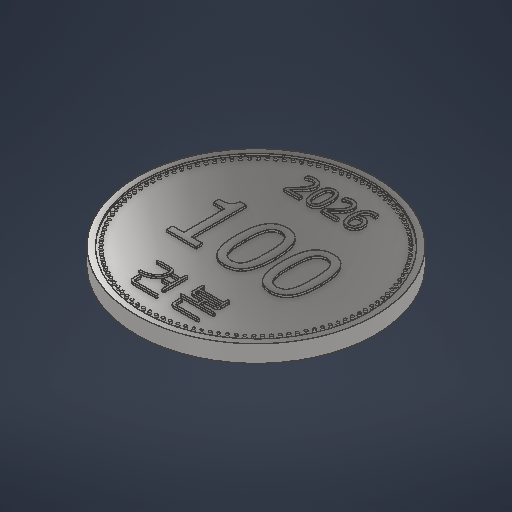
# Autodesk Inventor part: 비교용 100원 모델링
Saved by Autodesk Inventor 2027.1 (Build 311270010, 270A)
## iProperties
Created: 2026-09-27
Part Number: 비교용 100원 모델링
Material: 스테인리스스틸
Document SubType Name: Modeling
Designer: work
Density: 8 g/cm^3
Appearance: 반연마
Author: work
Autodesk Inventor part; units mm, degrees
ref_plane "YZ Plane" through (0, 0, 0) normal (1, 0, 0) x (0, 1, 0)
ref_plane "XZ Plane" through (0, 0, 0) normal (0, 1, 0) x (-1, 0, 0)
ref_plane "XY Plane" through (0, 0, 0) normal (0, 0, 1) x (1, 0, 0)
sketch "스케치1" plane through (0, 0, 0) normal (0, 1, 0) x (-1, 0, 0)
  circle A0 centre (0, 0) radius 12
  dimension "d0" = 24
  constraints: 1 centre point, 1 coincident
  measures "d0" diameter of A0
extrude "돌출1" add sketch "스케치1" along normal blind 1.5
sketch "스케치2" plane through (0, 1.5, 0) normal (0, 1, 0) x (1, 0, 0)
  circle A0 centre (0, 0) radius 12 projected
  circle A1 centre (0, 0) radius 11.4
  line L0 (0, 0) -> (-11, 0) construction
  circle A2 centre (-11, 0) radius 0.15
  line L1 (0, 0) -> (-10.9821, -0.628) construction
  circle A3 centre (-10.9821, -0.628) radius 0.15
  line L2 (0, 0) -> (-10.9283, -1.2539) construction
  circle A4 centre (-10.9283, -1.2539) radius 0.15
  line L3 (0, 0) -> (-10.8389, -1.8757) construction
  circle A5 centre (-10.8389, -1.8757) radius 0.15
  line L4 (0, 0) -> (-10.7141, -2.4915) construction
  circle A6 centre (-10.7141, -2.4915) radius 0.15
  line L5 (0, 0) -> (-10.5544, -3.0991) construction
  circle A7 centre (-10.5544, -3.0991) radius 0.15
  line L6 (0, 0) -> (-10.3603, -3.6965) construction
  circle A8 centre (-10.3603, -3.6965) radius 0.15
  line L7 (0, 0) -> (-10.1324, -4.282) construction
  circle A9 centre (-10.1324, -4.282) radius 0.15
  line L8 (0, 0) -> (-9.8714, -4.8534) construction
  circle A10 centre (-9.8714, -4.8534) radius 0.15
  line L9 (0, 0) -> (-9.5782, -5.4091) construction
  circle A11 centre (-9.5782, -5.4091) radius 0.15
  line L10 (0, 0) -> (-9.2538, -5.947) construction
  circle A12 centre (-9.2538, -5.947) radius 0.15
  line L11 (0, 0) -> (-8.8992, -6.4656) construction
  circle A13 centre (-8.8992, -6.4656) radius 0.15
  line L12 (0, 0) -> (-8.5156, -6.9631) construction
  circle A14 centre (-8.5156, -6.9631) radius 0.15
  line L13 (0, 0) -> (-8.1042, -7.4379) construction
  circle A15 centre (-8.1042, -7.4379) radius 0.15
  line L14 (0, 0) -> (-7.6663, -7.8884) construction
  circle A16 centre (-7.6663, -7.8884) radius 0.15
  line L15 (0, 0) -> (-7.2035, -8.3132) construction
  circle A17 centre (-7.2035, -8.3132) radius 0.15
  line L16 (0, 0) -> (-6.7171, -8.7109) construction
  circle A18 centre (-6.7171, -8.7109) radius 0.15
  line L17 (0, 0) -> (-6.2089, -9.0802) construction
  circle A19 centre (-6.2089, -9.0802) radius 0.15
  line L18 (0, 0) -> (-5.6804, -9.4198) construction
  circle A20 centre (-5.6804, -9.4198) radius 0.15
  line L19 (0, 0) -> (-5.1333, -9.7288) construction
  circle A21 centre (-5.1333, -9.7288) radius 0.15
  line L20 (0, 0) -> (-4.5696, -10.006) construction
  circle A22 centre (-4.5696, -10.006) radius 0.15
  line L21 (0, 0) -> (-3.9909, -10.2505) construction
  circle A23 centre (-3.9909, -10.2505) radius 0.15
  line L22 (0, 0) -> (-3.3992, -10.4616) construction
  circle A24 centre (-3.3992, -10.4616) radius 0.15
  line L23 (0, 0) -> (-2.7964, -10.6386) construction
  circle A25 centre (-2.7964, -10.6386) radius 0.15
  line L24 (0, 0) -> (-2.1845, -10.7809) construction
  circle A26 centre (-2.1845, -10.7809) radius 0.15
  line L25 (0, 0) -> (-1.5655, -10.888) construction
  circle A27 centre (-1.5655, -10.888) radius 0.15
  line L26 (0, 0) -> (-0.9413, -10.9596) construction
  circle A28 centre (-0.9413, -10.9596) radius 0.15
  line L27 (0, 0) -> (-0.3141, -10.9955) construction
  circle A29 centre (-0.3141, -10.9955) radius 0.15
  line L28 (0, 0) -> (0.3141, -10.9955) construction
  circle A30 centre (0.3141, -10.9955) radius 0.15
  line L29 (0, 0) -> (0.9413, -10.9596) construction
  circle A31 centre (0.9413, -10.9596) radius 0.15
  line L30 (0, 0) -> (1.5655, -10.888) construction
  circle A32 centre (1.5655, -10.888) radius 0.15
  line L31 (0, 0) -> (2.1845, -10.7809) construction
  circle A33 centre (2.1845, -10.7809) radius 0.15
  line L32 (0, 0) -> (2.7964, -10.6386) construction
  circle A34 centre (2.7964, -10.6386) radius 0.15
  line L33 (0, 0) -> (3.3992, -10.4616) construction
  circle A35 centre (3.3992, -10.4616) radius 0.15
  line L34 (0, 0) -> (3.9909, -10.2505) construction
  circle A36 centre (3.9909, -10.2505) radius 0.15
  line L35 (0, 0) -> (4.5696, -10.006) construction
  circle A37 centre (4.5696, -10.006) radius 0.15
  line L36 (0, 0) -> (5.1333, -9.7288) construction
  circle A38 centre (5.1333, -9.7288) radius 0.15
  line L37 (0, 0) -> (5.6804, -9.4198) construction
  circle A39 centre (5.6804, -9.4198) radius 0.15
  line L38 (0, 0) -> (6.2089, -9.0802) construction
  circle A40 centre (6.2089, -9.0802) radius 0.15
  line L39 (0, 0) -> (6.7171, -8.7109) construction
  circle A41 centre (6.7171, -8.7109) radius 0.15
  line L40 (0, 0) -> (7.2035, -8.3132) construction
  circle A42 centre (7.2035, -8.3132) radius 0.15
  line L41 (0, 0) -> (7.6663, -7.8884) construction
  circle A43 centre (7.6663, -7.8884) radius 0.15
  line L42 (0, 0) -> (8.1042, -7.4379) construction
  circle A44 centre (8.1042, -7.4379) radius 0.15
  line L43 (0, 0) -> (8.5156, -6.9631) construction
  circle A45 centre (8.5156, -6.9631) radius 0.15
  line L44 (0, 0) -> (8.8992, -6.4656) construction
  circle A46 centre (8.8992, -6.4656) radius 0.15
  line L45 (0, 0) -> (9.2538, -5.947) construction
  circle A47 centre (9.2538, -5.947) radius 0.15
  line L46 (0, 0) -> (9.5782, -5.4091) construction
  circle A48 centre (9.5782, -5.4091) radius 0.15
  line L47 (0, 0) -> (9.8714, -4.8534) construction
  circle A49 centre (9.8714, -4.8534) radius 0.15
  line L48 (0, 0) -> (10.1324, -4.282) construction
  circle A50 centre (10.1324, -4.282) radius 0.15
  line L49 (0, 0) -> (10.3603, -3.6965) construction
  circle A51 centre (10.3603, -3.6965) radius 0.15
  line L50 (0, 0) -> (10.5544, -3.0991) construction
  circle A52 centre (10.5544, -3.0991) radius 0.15
  line L51 (0, 0) -> (10.7141, -2.4915) construction
  circle A53 centre (10.7141, -2.4915) radius 0.15
  line L52 (0, 0) -> (10.8389, -1.8757) construction
  circle A54 centre (10.8389, -1.8757) radius 0.15
  line L53 (0, 0) -> (10.9283, -1.2539) construction
  circle A55 centre (10.9283, -1.2539) radius 0.15
  line L54 (0, 0) -> (10.9821, -0.628) construction
  circle A56 centre (10.9821, -0.628) radius 0.15
  line L55 (0, 0) -> (11, 0) construction
  circle A57 centre (11, 0) radius 0.15
  line L56 (0, 0) -> (10.9821, 0.628) construction
  circle A58 centre (10.9821, 0.628) radius 0.15
  line L57 (0, 0) -> (10.9283, 1.2539) construction
  circle A59 centre (10.9283, 1.2539) radius 0.15
  line L58 (0, 0) -> (10.8389, 1.8757) construction
  circle A60 centre (10.8389, 1.8757) radius 0.15
  line L59 (0, 0) -> (10.7141, 2.4915) construction
  circle A61 centre (10.7141, 2.4915) radius 0.15
  line L60 (0, 0) -> (10.5544, 3.0991) construction
  circle A62 centre (10.5544, 3.0991) radius 0.15
  line L61 (0, 0) -> (10.3603, 3.6965) construction
  circle A63 centre (10.3603, 3.6965) radius 0.15
  line L62 (0, 0) -> (10.1324, 4.282) construction
  circle A64 centre (10.1324, 4.282) radius 0.15
  line L63 (0, 0) -> (9.8714, 4.8534) construction
  circle A65 centre (9.8714, 4.8534) radius 0.15
  line L64 (0, 0) -> (9.5782, 5.4091) construction
  circle A66 centre (9.5782, 5.4091) radius 0.15
  line L65 (0, 0) -> (9.2538, 5.947) construction
  circle A67 centre (9.2538, 5.947) radius 0.15
  line L66 (0, 0) -> (8.8992, 6.4656) construction
  circle A68 centre (8.8992, 6.4656) radius 0.15
  line L67 (0, 0) -> (8.5156, 6.9631) construction
  circle A69 centre (8.5156, 6.9631) radius 0.15
  line L68 (0, 0) -> (8.1042, 7.4379) construction
  circle A70 centre (8.1042, 7.4379) radius 0.15
  line L69 (0, 0) -> (7.6663, 7.8884) construction
  circle A71 centre (7.6663, 7.8884) radius 0.15
  line L70 (0, 0) -> (7.2035, 8.3132) construction
  circle A72 centre (7.2035, 8.3132) radius 0.15
  line L71 (0, 0) -> (6.7171, 8.7109) construction
  circle A73 centre (6.7171, 8.7109) radius 0.15
  line L72 (0, 0) -> (6.2089, 9.0802) construction
  circle A74 centre (6.2089, 9.0802) radius 0.15
  line L73 (0, 0) -> (5.6804, 9.4198) construction
  circle A75 centre (5.6804, 9.4198) radius 0.15
  line L74 (0, 0) -> (5.1333, 9.7288) construction
  circle A76 centre (5.1333, 9.7288) radius 0.15
  line L75 (0, 0) -> (4.5696, 10.006) construction
  circle A77 centre (4.5696, 10.006) radius 0.15
  line L76 (0, 0) -> (3.9909, 10.2505) construction
  circle A78 centre (3.9909, 10.2505) radius 0.15
  line L77 (0, 0) -> (3.3992, 10.4616) construction
  circle A79 centre (3.3992, 10.4616) radius 0.15
  line L78 (0, 0) -> (2.7964, 10.6386) construction
  circle A80 centre (2.7964, 10.6386) radius 0.15
  line L79 (0, 0) -> (2.1845, 10.7809) construction
  circle A81 centre (2.1845, 10.7809) radius 0.15
  line L80 (0, 0) -> (1.5655, 10.888) construction
  circle A82 centre (1.5655, 10.888) radius 0.15
  line L81 (0, 0) -> (0.9413, 10.9596) construction
  circle A83 centre (0.9413, 10.9596) radius 0.15
  line L82 (0, 0) -> (0.3141, 10.9955) construction
  circle A84 centre (0.3141, 10.9955) radius 0.15
  line L83 (0, 0) -> (-0.3141, 10.9955) construction
  circle A85 centre (-0.3141, 10.9955) radius 0.15
  line L84 (0, 0) -> (-0.9413, 10.9596) construction
  circle A86 centre (-0.9413, 10.9596) radius 0.15
  line L85 (0, 0) -> (-1.5655, 10.888) construction
  circle A87 centre (-1.5655, 10.888) radius 0.15
  line L86 (0, 0) -> (-2.1845, 10.7809) construction
  circle A88 centre (-2.1845, 10.7809) radius 0.15
  line L87 (0, 0) -> (-2.7964, 10.6386) construction
  circle A89 centre (-2.7964, 10.6386) radius 0.15
  line L88 (0, 0) -> (-3.3992, 10.4616) construction
  circle A90 centre (-3.3992, 10.4616) radius 0.15
  line L89 (0, 0) -> (-3.9909, 10.2505) construction
  circle A91 centre (-3.9909, 10.2505) radius 0.15
  line L90 (0, 0) -> (-4.5696, 10.006) construction
  circle A92 centre (-4.5696, 10.006) radius 0.15
  line L91 (0, 0) -> (-5.1333, 9.7288) construction
  circle A93 centre (-5.1333, 9.7288) radius 0.15
  line L92 (0, 0) -> (-5.6804, 9.4198) construction
  circle A94 centre (-5.6804, 9.4198) radius 0.15
  line L93 (0, 0) -> (-6.2089, 9.0802) construction
  circle A95 centre (-6.2089, 9.0802) radius 0.15
  line L94 (0, 0) -> (-6.7171, 8.7109) construction
  circle A96 centre (-6.7171, 8.7109) radius 0.15
  line L95 (0, 0) -> (-7.2035, 8.3132) construction
  circle A97 centre (-7.2035, 8.3132) radius 0.15
  line L96 (0, 0) -> (-7.6663, 7.8884) construction
  circle A98 centre (-7.6663, 7.8884) radius 0.15
  line L97 (0, 0) -> (-8.1042, 7.4379) construction
  circle A99 centre (-8.1042, 7.4379) radius 0.15
  line L98 (0, 0) -> (-8.5156, 6.9631) construction
  circle A100 centre (-8.5156, 6.9631) radius 0.15
  line L99 (0, 0) -> (-8.8992, 6.4656) construction
  circle A101 centre (-8.8992, 6.4656) radius 0.15
  line L100 (0, 0) -> (-9.2538, 5.947) construction
  circle A102 centre (-9.2538, 5.947) radius 0.15
  line L101 (0, 0) -> (-9.5782, 5.4091) construction
  circle A103 centre (-9.5782, 5.4091) radius 0.15
  line L102 (0, 0) -> (-9.8714, 4.8534) construction
  circle A104 centre (-9.8714, 4.8534) radius 0.15
  line L103 (0, 0) -> (-10.1324, 4.282) construction
  circle A105 centre (-10.1324, 4.282) radius 0.15
  line L104 (0, 0) -> (-10.3603, 3.6965) construction
  circle A106 centre (-10.3603, 3.6965) radius 0.15
  line L105 (0, 0) -> (-10.5544, 3.0991) construction
  circle A107 centre (-10.5544, 3.0991) radius 0.15
  line L106 (0, 0) -> (-10.7141, 2.4915) construction
  circle A108 centre (-10.7141, 2.4915) radius 0.15
  line L107 (0, 0) -> (-10.8389, 1.8757) construction
  circle A109 centre (-10.8389, 1.8757) radius 0.15
  line L108 (0, 0) -> (-10.9283, 1.2539) construction
  circle A110 centre (-10.9283, 1.2539) radius 0.15
  line L109 (0, 0) -> (-10.9821, 0.628) construction
  circle A111 centre (-10.9821, 0.628) radius 0.15
  dimension "d4" = 11
  dimension "d5" = 0.3
  dimension "d8" = 360
  dimension "d10" = 22.8
  constraints: 220 end point, 113 coincident, 111 centre point, 1 horizontal, 549 other
  measures "d4" distance of A0.centre L0.end
  measures "d5" diameter of A2
  measures "d10" diameter of A1
extrude "돌출2" add sketch "스케치2" along normal blind 0.2
sketch "스케치3" plane through (0, 1.5, 0) normal (0, 1, 0) x (1, 0, 0)
  line L0 (-6.8662, 3.1761) -> (6.8662, 3.1761) construction
  line L1 (6.8662, 3.1761) -> (6.8662, -3.1761) construction
  line L2 (6.8662, -3.1761) -> (-6.8662, -3.1761) construction
  line L3 (-6.8662, -3.1761) -> (-6.8662, 3.1761) construction
  line L4 (-2.966, -3.0475) -> (-5.9418, -3.0475)
  line L5 (-5.9418, -3.0475) -> (-5.9418, -2.4247)
  line L6 (-5.9418, -2.4247) -> (-4.8345, -2.4247)
  line L7 (-4.8345, -2.4247) -> (-4.8345, 1.6634)
  line L8 (-4.8345, 1.6634) -> (-5.9418, 1.6634)
  line L9 (-5.9418, 1.6634) -> (-5.9418, 2.222)
  spline S0 degree 2 poles (-5.9418, 2.222) (-5.314, 2.222) (-4.7208, 2.5779) (-4.6813, 3.0722) knots 0 0 0 1 2 2 2
  line L10 (-4.6813, 3.0722) -> (-4.0485, 3.0722)
  line L11 (-4.0485, 3.0722) -> (-4.0485, -2.4247)
  line L12 (-4.0485, -2.4247) -> (-2.966, -2.4247)
  line L13 (-2.966, -2.4247) -> (-2.966, -3.0475)
  spline S1 degree 2 poles (1.9526, 0.0025) (1.9526, -1.6387) (0.9985, -3.1761) (0.0049, -3.1761) knots 0 0 0 1 2 2 2
  spline S2 degree 2 poles (0.0049, -3.1761) (-1.0035, -3.1761) (-1.9477, -1.609) (-1.9477, -0.0025) knots 0 0 0 1 2 2 2
  spline S3 degree 2 poles (-1.9477, -0.0025) (-1.9477, 1.6486) (-0.9936, 3.1761) (0.0049, 3.1761) knots 0 0 0 1 2 2 2
  spline S4 degree 2 poles (0.0049, 3.1761) (1.0084, 3.1761) (1.9526, 1.5942) (1.9526, 0.0025) knots 0 0 0 1 2 2 2
  spline S5 degree 2 poles (0.9046, -1.8562) (1.0233, -1.5547) (1.1221, -0.6253) (1.1221, 0.0025) knots 0 0 0 1 2 2 2
  spline S6 degree 2 poles (1.1221, 0.0025) (1.1221, 0.6303) (1.0233, 1.5547) (0.8997, 1.8661) knots 0 0 0 1 2 2 2
  spline S7 degree 2 poles (0.8997, 1.8661) (0.7761, 2.1775) (0.346, 2.4988) (0.0049, 2.4988) knots 0 0 0 1 2 2 2
  spline S8 degree 2 poles (0.0049, 2.4988) (-0.3361, 2.4988) (-0.7761, 2.1775) (-0.9046, 1.8562) knots 0 0 0 1 2 2 2
  spline S9 degree 2 poles (-0.9046, 1.8562) (-1.0282, 1.5448) (-1.1172, 0.5957) (-1.1172, -0.0025) knots 0 0 0 1 2 2 2
  spline S10 degree 2 poles (-1.1172, -0.0025) (-1.1172, -0.6451) (-1.0381, -1.5052) (-0.9096, -1.8414) knots 0 0 0 1 2 2 2
  spline S11 degree 2 poles (-0.9096, -1.8414) (-0.7909, -2.1577) (-0.351, -2.4988) (0.0049, -2.4988) knots 0 0 0 1 2 2 2
  spline S12 degree 2 poles (0.0049, -2.4988) (0.3411, -2.4988) (0.781, -2.1775) (0.9046, -1.8562) knots 0 0 0 1 2 2 2
  spline S13 degree 2 poles (6.5301, 0.0025) (6.5301, -1.6387) (5.576, -3.1761) (4.5824, -3.1761) knots 0 0 0 1 2 2 2
  spline S14 degree 2 poles (4.5824, -3.1761) (3.574, -3.1761) (2.6298, -1.609) (2.6298, -0.0025) knots 0 0 0 1 2 2 2
  spline S15 degree 2 poles (2.6298, -0.0025) (2.6298, 1.6486) (3.5839, 3.1761) (4.5824, 3.1761) knots 0 0 0 1 2 2 2
  spline S16 degree 2 poles (4.5824, 3.1761) (5.5859, 3.1761) (6.5301, 1.5942) (6.5301, 0.0025) knots 0 0 0 1 2 2 2
  spline S17 degree 2 poles (5.4821, -1.8562) (5.6007, -1.5547) (5.6996, -0.6253) (5.6996, 0.0025) knots 0 0 0 1 2 2 2
  spline S18 degree 2 poles (5.6996, 0.0025) (5.6996, 0.6303) (5.6007, 1.5547) (5.4771, 1.8661) knots 0 0 0 1 2 2 2
  spline S19 degree 2 poles (5.4771, 1.8661) (5.3536, 2.1775) (4.9235, 2.4988) (4.5824, 2.4988) knots 0 0 0 1 2 2 2
  spline S20 degree 2 poles (4.5824, 2.4988) (4.2413, 2.4988) (3.8014, 2.1775) (3.6729, 1.8562) knots 0 0 0 1 2 2 2
  spline S21 degree 2 poles (3.6729, 1.8562) (3.5493, 1.5448) (3.4603, 0.5957) (3.4603, -0.0025) knots 0 0 0 1 2 2 2
  spline S22 degree 2 poles (3.4603, -0.0025) (3.4603, -0.6451) (3.5394, -1.5052) (3.6679, -1.8414) knots 0 0 0 1 2 2 2
  spline S23 degree 2 poles (3.6679, -1.8414) (3.7865, -2.1577) (4.2265, -2.4988) (4.5824, -2.4988) knots 0 0 0 1 2 2 2
  spline S24 degree 2 poles (4.5824, -2.4988) (4.9186, -2.4988) (5.3585, -2.1775) (5.4821, -1.8562) knots 0 0 0 1 2 2 2
  point P0 (0, 0)
  point P1 (0, 3.1761)
  point P2 (-6.8662, 0)
  constraints: 2 midpoint, 1 horizontal alignment, 1 vertical alignment, 2 other
sketch "스케치4" plane through (0, 1.5, 0) normal (0, 1, 0) x (1, 0, 0)
  line L0 (-4.1916, -6) -> (4.1916, -6) construction
  line L1 (4.1916, -6) -> (4.1916, -9.3246) construction
  line L2 (4.1916, -9.3246) -> (-4.1916, -9.3246) construction
  line L3 (-4.1916, -9.3246) -> (-4.1916, -6) construction
  line L4 (-4.7627, 9.1764) -> (4.7627, 9.1764) construction
  line L5 (4.7627, 9.1764) -> (4.7627, 6) construction
  line L6 (4.7627, 6) -> (-4.7627, 6) construction
  line L7 (-4.7627, 6) -> (-4.7627, 9.1764) construction
  line L8 (-0.7781, -8.3663) -> (-0.7781, -6.1235)
  spline S0 degree 2 poles (-0.7781, -6.1235) (-0.7781, -6.0618) (-0.8176, -6.0296) knots 0 0 0 1 1 1
  spline S1 degree 2 poles (-0.8176, -6.0296) (-0.8522, -6) (-0.8991, -6) knots 0 0 0 1 1 1
  spline S2 degree 2 poles (-0.8991, -6) (-0.9534, -6) (-0.9855, -6.0296) knots 0 0 0 1 1 1
  spline S3 degree 2 poles (-0.9855, -6.0296) (-1.0226, -6.0618) (-1.0226, -6.1235) knots 0 0 0 1 1 1
  line L9 (-1.0226, -6.1235) -> (-1.0226, -6.5483)
  line L10 (-1.0226, -6.5483) -> (-1.7315, -6.5483)
  spline S4 degree 2 poles (-1.7315, -6.5483) (-1.7883, -6.5483) (-1.8204, -6.5805) knots 0 0 0 1 1 1
  spline S5 degree 2 poles (-1.8204, -6.5805) (-1.85, -6.6101) (-1.8451, -6.6546) knots 0 0 0 1 1 1
  spline S6 degree 2 poles (-1.8451, -6.6546) (-1.8402, -6.6965) (-1.8081, -6.7237) knots 0 0 0 1 1 1
  spline S7 degree 2 poles (-1.8081, -6.7237) (-1.7685, -6.7608) (-1.7018, -6.7608) knots 0 0 0 1 1 1
  line L11 (-1.7018, -6.7608) -> (-1.0226, -6.7608)
  line L12 (-1.0226, -6.7608) -> (-1.0226, -7.4771)
  line L13 (-1.0226, -7.4771) -> (-1.7414, -7.4771)
  spline S8 degree 2 poles (-1.7414, -7.4771) (-1.8056, -7.4771) (-1.8426, -7.5067) knots 0 0 0 1 1 1
  spline S9 degree 2 poles (-1.8426, -7.5067) (-1.8797, -7.5388) (-1.8797, -7.5808) knots 0 0 0 1 1 1
  spline S10 degree 2 poles (-1.8797, -7.5808) (-1.8797, -7.6203) (-1.8476, -7.6549) knots 0 0 0 1 1 1
  spline S11 degree 2 poles (-1.8476, -7.6549) (-1.8105, -7.687) (-1.7488, -7.687) knots 0 0 0 1 1 1
  line L14 (-1.7488, -7.687) -> (-1.0226, -7.687)
  line L15 (-1.0226, -7.687) -> (-1.0226, -8.3663)
  spline S12 degree 2 poles (-1.0226, -8.3663) (-1.0226, -8.428) (-0.9855, -8.4651) knots 0 0 0 1 1 1
  spline S13 degree 2 poles (-0.9855, -8.4651) (-0.9534, -8.4972) (-0.8991, -8.4972) knots 0 0 0 1 1 1
  spline S14 degree 2 poles (-0.8991, -8.4972) (-0.8522, -8.4972) (-0.8176, -8.4651) knots 0 0 0 1 1 1
  spline S15 degree 2 poles (-0.8176, -8.4651) (-0.7781, -8.428) (-0.7781, -8.3663) knots 0 0 0 1 1 1
  line L16 (-2.3564, -6.1235) -> (-3.5815, -6.1235)
  spline S16 degree 2 poles (-3.5815, -6.1235) (-3.6976, -6.1235) (-3.6927, -6.2272) knots 0 0 0 1 1 1
  spline S17 degree 2 poles (-3.6927, -6.2272) (-3.6927, -6.3335) (-3.5791, -6.3335) knots 0 0 0 1 1 1
  line L17 (-3.5791, -6.3335) -> (-2.3515, -6.3335)
  spline S18 degree 2 poles (-2.3515, -6.3335) (-2.2601, -6.3335) (-2.2156, -6.3754) knots 0 0 0 1 1 1
  spline S19 degree 2 poles (-2.2156, -6.3754) (-2.1662, -6.415) (-2.1662, -6.5014) knots 0 0 0 1 1 1
  line L18 (-2.1662, -6.5014) -> (-2.1662, -6.7015)
  spline S20 degree 2 poles (-2.1662, -6.7015) (-2.1662, -7.1757) (-2.5515, -7.4894) knots 0 0 0 1 1 1
  spline S21 degree 2 poles (-2.5515, -7.4894) (-2.9517, -7.8155) (-3.6433, -7.8649) knots 0 0 0 1 1 1
  spline S22 degree 2 poles (-3.6433, -7.8649) (-3.705, -7.8649) (-3.7421, -7.897) knots 0 0 0 1 1 1
  spline S23 degree 2 poles (-3.7421, -7.897) (-3.7717, -7.9316) (-3.7668, -7.9711) knots 0 0 0 1 1 1
  spline S24 degree 2 poles (-3.7668, -7.9711) (-3.7618, -8.018) (-3.7297, -8.0452) knots 0 0 0 1 1 1
  spline S25 degree 2 poles (-3.7297, -8.0452) (-3.6927, -8.0748) (-3.6309, -8.0748) knots 0 0 0 1 1 1
  spline S26 degree 2 poles (-3.6309, -8.0748) (-2.8702, -8.0254) (-2.3959, -7.6327) knots 0 0 0 1 1 1
  spline S27 degree 2 poles (-2.3959, -7.6327) (-1.934, -7.2523) (-1.934, -6.704) knots 0 0 0 1 1 1
  line L19 (-1.934, -6.704) -> (-1.934, -6.4841)
  spline S28 degree 2 poles (-1.934, -6.4841) (-1.934, -6.3112) (-2.0476, -6.2174) knots 0 0 0 1 1 1
  spline S29 degree 2 poles (-2.0476, -6.2174) (-2.1637, -6.1235) (-2.3564, -6.1235) knots 0 0 0 1 1 1
  spline S30 degree 2 poles (-3.1641, -8.4157) (-3.1641, -8.349) (-3.2036, -8.3119) knots 0 0 0 1 1 1
  spline S31 degree 2 poles (-3.2036, -8.3119) (-3.2382, -8.2798) (-3.2851, -8.2798) knots 0 0 0 1 1 1
  spline S32 degree 2 poles (-3.2851, -8.2798) (-3.3395, -8.2798) (-3.3716, -8.3119) knots 0 0 0 1 1 1
  spline S33 degree 2 poles (-3.3716, -8.3119) (-3.4086, -8.349) (-3.4086, -8.4157) knots 0 0 0 1 1 1
  line L20 (-3.4086, -8.4157) -> (-3.4086, -8.9591)
  spline S34 degree 2 poles (-3.4086, -8.9591) (-3.4086, -9.1394) (-3.295, -9.2333) knots 0 0 0 1 1 1
  spline S35 degree 2 poles (-3.295, -9.2333) (-3.1888, -9.3246) (-3.0035, -9.3246) knots 0 0 0 1 1 1
  line L21 (-3.0035, -9.3246) -> (-0.7558, -9.3246)
  spline S36 degree 2 poles (-0.7558, -9.3246) (-0.6546, -9.3246) (-0.6546, -9.2184) knots 0 0 0 1 1 1
  spline S37 degree 2 poles (-0.6546, -9.2184) (-0.6546, -9.1147) (-0.7558, -9.1147) knots 0 0 0 1 1 1
  line L22 (-0.7558, -9.1147) -> (-2.964, -9.1147)
  spline S38 degree 2 poles (-2.964, -9.1147) (-3.0826, -9.1147) (-3.1221, -9.0776) knots 0 0 0 1 1 1
  spline S39 degree 2 poles (-3.1221, -9.0776) (-3.1641, -9.0381) (-3.1641, -8.927) knots 0 0 0 1 1 1
  line L23 (-3.1641, -8.927) -> (-3.1641, -8.4157)
  line L24 (1.1016, -7.3363) -> (3.0875, -7.3363)
  spline S40 degree 2 poles (3.0875, -7.3363) (3.2802, -7.3363) (3.379, -7.2424) knots 0 0 0 1 1 1
  spline S41 degree 2 poles (3.379, -7.2424) (3.4803, -7.1486) (3.4803, -6.9757) knots 0 0 0 1 1 1
  line L25 (3.4803, -6.9757) -> (3.4803, -6.1778)
  spline S42 degree 2 poles (3.4803, -6.1778) (3.4803, -6.121) (3.4407, -6.0865) knots 0 0 0 1 1 1
  spline S43 degree 2 poles (3.4407, -6.0865) (3.4062, -6.0543) (3.3592, -6.0543) knots 0 0 0 1 1 1
  spline S44 degree 2 poles (3.3592, -6.0543) (3.3049, -6.0543) (3.2728, -6.0865) knots 0 0 0 1 1 1
  spline S45 degree 2 poles (3.2728, -6.0865) (3.2357, -6.1186) (3.2357, -6.1778) knots 0 0 0 1 1 1
  line L26 (3.2357, -6.1778) -> (3.2357, -6.4989)
  line L27 (3.2357, -6.4989) -> (0.9559, -6.4989)
  line L28 (0.9559, -6.4989) -> (0.9559, -6.1877)
  spline S46 degree 2 poles (0.9559, -6.1877) (0.9559, -6.126) (0.9164, -6.0889) knots 0 0 0 1 1 1
  spline S47 degree 2 poles (0.9164, -6.0889) (0.8818, -6.0568) (0.8349, -6.0568) knots 0 0 0 1 1 1
  spline S48 degree 2 poles (0.8349, -6.0568) (0.7805, -6.0568) (0.7484, -6.0889) knots 0 0 0 1 1 1
  spline S49 degree 2 poles (0.7484, -6.0889) (0.7114, -6.126) (0.7114, -6.1877) knots 0 0 0 1 1 1
  line L29 (0.7114, -6.1877) -> (0.7114, -7.0004)
  spline S50 degree 2 poles (0.7114, -7.0004) (0.7114, -7.1609) (0.8126, -7.2449) knots 0 0 0 1 1 1
  spline S51 degree 2 poles (0.8126, -7.2449) (0.9164, -7.3363) (1.1016, -7.3363) knots 0 0 0 1 1 1
  line L30 (3.2357, -6.7089) -> (3.2357, -6.9633)
  spline S52 degree 2 poles (3.2357, -6.9633) (3.2357, -7.0498) (3.1913, -7.0843) knots 0 0 0 1 1 1
  spline S53 degree 2 poles (3.1913, -7.0843) (3.1443, -7.1263) (3.048, -7.1263) knots 0 0 0 1 1 1
  line L31 (3.048, -7.1263) -> (1.1288, -7.1263)
  spline S54 degree 2 poles (1.1288, -7.1263) (1.0349, -7.1263) (0.9929, -7.0843) knots 0 0 0 1 1 1
  spline S55 degree 2 poles (0.9929, -7.0843) (0.9559, -7.0498) (0.9559, -6.9658) knots 0 0 0 1 1 1
  line L32 (0.9559, -6.9658) -> (0.9559, -6.7089)
  line L33 (0.9559, -6.7089) -> (3.2357, -6.7089)
  line L34 (3.6828, -7.8451) -> (2.2107, -7.8451)
  line L35 (2.2107, -7.8451) -> (2.2107, -7.356)
  spline S56 degree 2 poles (2.2107, -7.356) (2.2107, -7.3066) (2.1687, -7.2819) knots 0 0 0 1 1 1
  spline S57 degree 2 poles (2.1687, -7.2819) (2.1366, -7.2572) (2.0921, -7.2572) knots 0 0 0 1 1 1
  spline S58 degree 2 poles (2.0921, -7.2572) (2.0427, -7.2572) (2.0106, -7.2869) knots 0 0 0 1 1 1
  spline S59 degree 2 poles (2.0106, -7.2869) (1.9735, -7.314) (1.9735, -7.3684) knots 0 0 0 1 1 1
  line L36 (1.9735, -7.3684) -> (1.9735, -7.8451)
  line L37 (1.9735, -7.8451) -> (0.5088, -7.8451)
  spline S60 degree 2 poles (0.5088, -7.8451) (0.3903, -7.8451) (0.3853, -7.9488) knots 0 0 0 1 1 1
  spline S61 degree 2 poles (0.3853, -7.9488) (0.3853, -8.0551) (0.4989, -8.0551) knots 0 0 0 1 1 1
  line L38 (0.4989, -8.0551) -> (3.6877, -8.0551)
  spline S62 degree 2 poles (3.6877, -8.0551) (3.7421, -8.0551) (3.7742, -8.0229) knots 0 0 0 1 1 1
  spline S63 degree 2 poles (3.7742, -8.0229) (3.8063, -7.9884) (3.8063, -7.9488) knots 0 0 0 1 1 1
  spline S64 degree 2 poles (3.8063, -7.9488) (3.8063, -7.9069) (3.7742, -7.8747) knots 0 0 0 1 1 1
  spline S65 degree 2 poles (3.7742, -7.8747) (3.7421, -7.8451) (3.6828, -7.8451) knots 0 0 0 1 1 1
  spline S66 degree 2 poles (0.9559, -8.4157) (0.9559, -8.344) (0.9164, -8.3045) knots 0 0 0 1 1 1
  spline S67 degree 2 poles (0.9164, -8.3045) (0.8818, -8.2675) (0.8349, -8.2675) knots 0 0 0 1 1 1
  spline S68 degree 2 poles (0.8349, -8.2675) (0.7805, -8.2675) (0.7484, -8.3045) knots 0 0 0 1 1 1
  spline S69 degree 2 poles (0.7484, -8.3045) (0.7114, -8.3416) (0.7114, -8.4157) knots 0 0 0 1 1 1
  line L39 (0.7114, -8.4157) -> (0.7114, -8.964)
  spline S70 degree 2 poles (0.7114, -8.964) (0.7114, -9.1246) (0.8052, -9.2234) knots 0 0 0 1 1 1
  spline S71 degree 2 poles (0.8052, -9.2234) (0.8991, -9.3246) (1.0646, -9.3246) knots 0 0 0 1 1 1
  line L40 (1.0646, -9.3246) -> (3.4185, -9.3246)
  spline S72 degree 2 poles (3.4185, -9.3246) (3.5247, -9.3246) (3.5247, -9.2184) knots 0 0 0 1 1 1
  spline S73 degree 2 poles (3.5247, -9.2184) (3.5247, -9.1147) (3.4185, -9.1147) knots 0 0 0 1 1 1
  line L41 (3.4185, -9.1147) -> (1.1535, -9.1147)
  spline S74 degree 2 poles (1.1535, -9.1147) (1.0374, -9.1147) (0.9979, -9.0776) knots 0 0 0 1 1 1
  spline S75 degree 2 poles (0.9979, -9.0776) (0.9559, -9.0381) (0.9559, -8.927) knots 0 0 0 1 1 1
  line L42 (0.9559, -8.927) -> (0.9559, -8.4157)
  line L43 (-2.028, 6.3382) -> (-3.5697, 6.3382)
  line L44 (-3.5697, 6.3382) -> (-3.5697, 6.6928)
  spline S76 degree 2 poles (-3.5697, 6.6928) (-3.4036, 6.8488) (-3.1078, 7.1385) (-2.966, 7.2945) knots 0 0 0 1 2 2 2
  spline S77 degree 2 poles (-2.966, 7.2945) (-2.6803, 7.6085) (-2.4716, 7.9853) (-2.4716, 8.1859) knots 0 0 0 1 2 2 2
  spline S78 degree 2 poles (-2.4716, 8.1859) (-2.4716, 8.2912) (-2.5365, 8.4492) (-2.5952, 8.4999) knots 0 0 0 1 2 2 2
  spline S79 degree 2 poles (-2.5952, 8.4999) (-2.654, 8.5505) (-2.8079, 8.6012) (-2.9011, 8.6012) knots 0 0 0 1 2 2 2
  spline S80 degree 2 poles (-2.9011, 8.6012) (-2.9903, 8.6012) (-3.1726, 8.5566) (-3.2557, 8.5222) knots 0 0 0 1 2 2 2
  spline S81 degree 2 poles (-3.2557, 8.5222) (-3.3266, 8.4938) (-3.4583, 8.4128) (-3.4988, 8.3844) knots 0 0 0 1 2 2 2
  line L45 (-3.4988, 8.3844) -> (-3.517, 8.3844)
  line L46 (-3.517, 8.3844) -> (-3.517, 8.741)
  spline S82 degree 2 poles (-3.517, 8.741) (-3.4137, 8.7916) (-3.0429, 8.8909) (-2.8768, 8.8909) knots 0 0 0 1 2 2 2
  spline S83 degree 2 poles (-2.8768, 8.8909) (-2.5263, 8.8909) (-2.1313, 8.5201) (-2.1313, 8.2041) knots 0 0 0 1 2 2 2
  spline S84 degree 2 poles (-2.1313, 8.2041) (-2.1313, 8.0562) (-2.2002, 7.809) (-2.2609, 7.7037) knots 0 0 0 1 2 2 2
  spline S85 degree 2 poles (-2.2609, 7.7037) (-2.3217, 7.5943) (-2.498, 7.3795) (-2.5952, 7.2762) knots 0 0 0 1 2 2 2
  spline S86 degree 2 poles (-2.5952, 7.2762) (-2.7532, 7.104) (-3.1402, 6.7353) (-3.2557, 6.6279) knots 0 0 0 1 2 2 2
  line L47 (-3.2557, 6.6279) -> (-2.028, 6.6279)
  line L48 (-2.028, 6.6279) -> (-2.028, 6.3382)
  spline S87 degree 2 poles (-0.1378, 7.5882) (-0.1378, 6.9156) (-0.5288, 6.2855) (-0.936, 6.2855) knots 0 0 0 1 2 2 2
  spline S88 degree 2 poles (-0.936, 6.2855) (-1.3493, 6.2855) (-1.7362, 6.9278) (-1.7362, 7.5862) knots 0 0 0 1 2 2 2
  spline S89 degree 2 poles (-1.7362, 7.5862) (-1.7362, 8.2629) (-1.3452, 8.8889) (-0.936, 8.8889) knots 0 0 0 1 2 2 2
  spline S90 degree 2 poles (-0.936, 8.8889) (-0.5247, 8.8889) (-0.1378, 8.2406) (-0.1378, 7.5882) knots 0 0 0 1 2 2 2
  spline S91 degree 2 poles (-0.5673, 6.8265) (-0.5186, 6.9501) (-0.4781, 7.3309) (-0.4781, 7.5882) knots 0 0 0 1 2 2 2
  spline S92 degree 2 poles (-0.4781, 7.5882) (-0.4781, 7.8455) (-0.5186, 8.2244) (-0.5693, 8.352) knots 0 0 0 1 2 2 2
  spline S93 degree 2 poles (-0.5693, 8.352) (-0.6199, 8.4796) (-0.7962, 8.6113) (-0.936, 8.6113) knots 0 0 0 1 2 2 2
  spline S94 degree 2 poles (-0.936, 8.6113) (-1.0758, 8.6113) (-1.2561, 8.4796) (-1.3088, 8.3479) knots 0 0 0 1 2 2 2
  spline S95 degree 2 poles (-1.3088, 8.3479) (-1.3594, 8.2203) (-1.3959, 7.8313) (-1.3959, 7.5862) knots 0 0 0 1 2 2 2
  spline S96 degree 2 poles (-1.3959, 7.5862) (-1.3959, 7.3228) (-1.3635, 6.9703) (-1.3108, 6.8325) knots 0 0 0 1 2 2 2
  spline S97 degree 2 poles (-1.3108, 6.8325) (-1.2622, 6.7029) (-1.0818, 6.5631) (-0.936, 6.5631) knots 0 0 0 1 2 2 2
  spline S98 degree 2 poles (-0.936, 6.5631) (-0.7982, 6.5631) (-0.6179, 6.6948) (-0.5673, 6.8265) knots 0 0 0 1 2 2 2
  line L49 (1.7241, 6.3382) -> (0.1823, 6.3382)
  line L50 (0.1823, 6.3382) -> (0.1823, 6.6928)
  spline S99 degree 2 poles (0.1823, 6.6928) (0.3485, 6.8488) (0.6442, 7.1385) (0.7861, 7.2945) knots 0 0 0 1 2 2 2
  spline S100 degree 2 poles (0.7861, 7.2945) (1.0717, 7.6085) (1.2804, 7.9853) (1.2804, 8.1859) knots 0 0 0 1 2 2 2
  spline S101 degree 2 poles (1.2804, 8.1859) (1.2804, 8.2912) (1.2156, 8.4492) (1.1568, 8.4999) knots 0 0 0 1 2 2 2
  spline S102 degree 2 poles (1.1568, 8.4999) (1.0981, 8.5505) (0.9441, 8.6012) (0.8509, 8.6012) knots 0 0 0 1 2 2 2
  spline S103 degree 2 poles (0.8509, 8.6012) (0.7618, 8.6012) (0.5794, 8.5566) (0.4964, 8.5222) knots 0 0 0 1 2 2 2
  spline S104 degree 2 poles (0.4964, 8.5222) (0.4254, 8.4938) (0.2938, 8.4128) (0.2532, 8.3844) knots 0 0 0 1 2 2 2
  line L51 (0.2532, 8.3844) -> (0.235, 8.3844)
  line L52 (0.235, 8.3844) -> (0.235, 8.741)
  spline S105 degree 2 poles (0.235, 8.741) (0.3383, 8.7916) (0.7091, 8.8909) (0.8752, 8.8909) knots 0 0 0 1 2 2 2
  spline S106 degree 2 poles (0.8752, 8.8909) (1.2257, 8.8909) (1.6207, 8.5201) (1.6207, 8.2041) knots 0 0 0 1 2 2 2
  spline S107 degree 2 poles (1.6207, 8.2041) (1.6207, 8.0562) (1.5519, 7.809) (1.4911, 7.7037) knots 0 0 0 1 2 2 2
  spline S108 degree 2 poles (1.4911, 7.7037) (1.4303, 7.5943) (1.2541, 7.3795) (1.1568, 7.2762) knots 0 0 0 1 2 2 2
  spline S109 degree 2 poles (1.1568, 7.2762) (0.9988, 7.104) (0.6118, 6.7353) (0.4964, 6.6279) knots 0 0 0 1 2 2 2
  line L53 (0.4964, 6.6279) -> (1.7241, 6.6279)
  line L54 (1.7241, 6.6279) -> (1.7241, 6.3382)
  spline S110 degree 2 poles (3.6386, 7.1486) (3.6386, 6.9561) (3.5109, 6.63) (3.4036, 6.5206) knots 0 0 0 1 2 2 2
  spline S111 degree 2 poles (3.4036, 6.5206) (3.2921, 6.4051) (3.0126, 6.2855) (2.8444, 6.2855) knots 0 0 0 1 2 2 2
  spline S112 degree 2 poles (2.8444, 6.2855) (2.6763, 6.2855) (2.3987, 6.399) (2.2934, 6.5125) knots 0 0 0 1 2 2 2
  spline S113 degree 2 poles (2.2934, 6.5125) (2.1637, 6.6482) (2.0178, 7.104) (2.0178, 7.4363) knots 0 0 0 1 2 2 2
  spline S114 degree 2 poles (2.0178, 7.4363) (2.0178, 7.7625) (2.1515, 8.2872) (2.2913, 8.4817) knots 0 0 0 1 2 2 2
  spline S115 degree 2 poles (2.2913, 8.4817) (2.4271, 8.6721) (2.8566, 8.8848) (3.1382, 8.8848) knots 0 0 0 1 2 2 2
  spline S116 degree 2 poles (3.1382, 8.8848) (3.2212, 8.8848) (3.3671, 8.8686) (3.4218, 8.8504) knots 0 0 0 1 2 2 2
  line L55 (3.4218, 8.8504) -> (3.4218, 8.5283)
  line L56 (3.4218, 8.5283) -> (3.4076, 8.5283)
  spline S117 degree 2 poles (3.4076, 8.5283) (3.361, 8.5526) (3.1908, 8.5951) (3.0936, 8.5951) knots 0 0 0 1 2 2 2
  spline S118 degree 2 poles (3.0936, 8.5951) (2.7816, 8.5951) (2.3987, 8.1737) (2.3622, 7.7604) knots 0 0 0 1 2 2 2
  spline S119 degree 2 poles (2.3622, 7.7604) (2.4818, 7.8435) (2.733, 7.9347) (2.8829, 7.9347) knots 0 0 0 1 2 2 2
  spline S120 degree 2 poles (2.8829, 7.9347) (3.0288, 7.9347) (3.2476, 7.8759) (3.3671, 7.7868) knots 0 0 0 1 2 2 2
  spline S121 degree 2 poles (3.3671, 7.7868) (3.5049, 7.6834) (3.6386, 7.3633) (3.6386, 7.1486) knots 0 0 0 1 2 2 2
  spline S122 degree 2 poles (3.2982, 7.1344) (3.2982, 7.2884) (3.2172, 7.4971) (3.128, 7.57) knots 0 0 0 1 2 2 2
  spline S123 degree 2 poles (3.128, 7.57) (3.0612, 7.6227) (2.8951, 7.6571) (2.8079, 7.6571) knots 0 0 0 1 2 2 2
  spline S124 degree 2 poles (2.8079, 7.6571) (2.6904, 7.6571) (2.4696, 7.5862) (2.3622, 7.5193) knots 0 0 0 1 2 2 2
  spline S125 degree 2 poles (2.3622, 7.5193) (2.3602, 7.4829) (2.3562, 7.414) (2.3562, 7.3613) knots 0 0 0 1 2 2 2
  spline S126 degree 2 poles (2.3562, 7.3613) (2.3562, 7.102) (2.4575, 6.7839) (2.5344, 6.7009) knots 0 0 0 1 2 2 2
  spline S127 degree 2 poles (2.5344, 6.7009) (2.6053, 6.6219) (2.7593, 6.559) (2.8464, 6.559) knots 0 0 0 1 2 2 2
  spline S128 degree 2 poles (2.8464, 6.559) (3.049, 6.559) (3.2982, 6.8467) (3.2982, 7.1344) knots 0 0 0 1 2 2 2
  point P0 (0, 0)
  point P1 (0, -6)
  point P2 (0, 6)
  dimension "d13" = 6
  dimension "d14" = 6
  constraints: 2 midpoint, 2 vertical alignment, 4 other
  measures "d13" distance of point (0, -6) point (0, 0)
  measures "d14" distance of point (0, 0) point (0, 6)
extrude "돌출3" add sketch "스케치3" along normal blind 0.2
extrude "돌출4" add sketch "스케치4" along normal blind 0.2 contours S15 S14 S13 S12 L15 L14 S11 S10 S9 S8 L13 L12 L11 S7 S6 S5 S4 L10 L9 S3 S2 S1 S0 L8 | S29 S28 L19 S27 S26 S25 S24 S23 S22 S21 S20 L18 S19 S18 L17 S17 S16 L16 | L23 S39 S38 L22 S37 S36 L21 S35 S34 L20 S33 S32 S31 S30 | S51 S50 L29 S49 S48 S47 S46 L28 L27 L26 S45 S44 S43 S42 L25 S41 S40 L24 S56 S57 S58 S59 | S59 S58 S57 S56 L24 | L24 S56 L35 L34 S65 S64 S63 S62 L38 S61 S60 L37 L36 S59 | L42 S75 S74 L41 S73 S72 L40 S71 S70 L39 S69 S68 S67 S66
extrude "돌출5" add sketch "스케치4" along normal blind 0.2 contours L43 L44 S76 S77 S78 S79 S80 S81 L45 L46 S82 S83 S84 S85 S86 L47 L48 | S87 S88 S89 S90 | L49 L50 S99 S100 S101 S102 S103 S104 L51 L52 S105 S106 S107 S108 S109 L53 L54 | S110 S111 S112 S113 S114 S115 S116 L55 L56 S117 S118 S119 S120 S121
